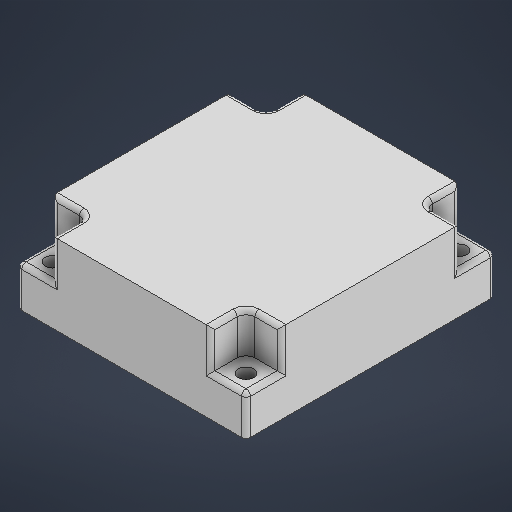
# Autodesk Inventor part: Voltage Regulator Module
Saved by Autodesk Inventor 2026.2 (Build 302298010, 298A)
## iProperties
Created: 2026-05-14
Part Number: Voltage Regulator Module
Material: Generic
Document SubType Name: Modeling
Designer: User
Density: 1 g/cm^3
Appearance: Default
Author: User
Autodesk Inventor part; units mm, degrees
ref_plane "YZ Plane" through (0, 0, 0) normal (1, 0, 0) x (0, 1, 0)
ref_plane "XZ Plane" through (0, 0, 0) normal (0, 1, 0) x (-1, 0, 0)
ref_plane "XY Plane" through (0, 0, 0) normal (0, 0, 1) x (1, 0, 0)
sketch "Sketch1" plane through (0, 0, 0) normal (0, 1, 0) x (-1, 0, 0)
  line L0 (24.75, 28) -> (-24.75, 28)
  line L1 (-25.75, 27) -> (-25.75, -27)
  line L2 (-24.75, -28) -> (24.75, -28)
  line L3 (25.75, -27) -> (25.75, 27)
  line L4 (25.75, 28) -> (-25.75, -28) construction
  line L5 (-25.75, 28) -> (25.75, -28) construction
  arc A0 (-25.75, -27) -> (-24.75, -28) centre (-24.75, -27) ccw
  arc A1 (-24.75, 28) -> (-25.75, 27) centre (-24.75, 27) ccw
  arc A2 (25.75, 27) -> (24.75, 28) centre (24.75, 27) ccw
  arc A3 (24.75, -28) -> (25.75, -27) centre (24.75, -27) ccw
  point P0 (0, 0)
  dimension "d0" = 51.5
  dimension "d1" = 56
  dimension "d16" = 1
  constraints: 12 end point, 8 point on circle, 8 point on line, 8 tangent, 4 centre point, 3 equal radius, 2 midpoint, 2 parallel, 1 horizontal, 1 perpendicular
  measures "d0" distance of L5.end L4.end
  measures "d1" distance of L4.end L5.start
  measures "d16" radius of A0
extrude "Extrusion1" add sketch "Sketch1" along normal blind 18
sketch "Sketch2" plane through (0, 18, 0) normal (0, 1, 0) x (1, 0, 0)
  line L0 (-24.75, -28) -> (24.75, -28) projected
  line L1 (-25.75, -28) -> (-17.75, -28)
  line L2 (-17.75, -28) -> (-17.75, -22)
  line L3 (-19.75, -20) -> (-25.75, -20)
  line L4 (-25.75, -20) -> (-25.75, -28)
  line L5 (24.75, 28) -> (-24.75, 28) projected
  line L6 (-25.75, 28) -> (-17.75, 28)
  line L7 (-17.75, 28) -> (-17.75, 22)
  line L8 (-19.75, 20) -> (-25.75, 20)
  line L9 (-25.75, 20) -> (-25.75, 28)
  line L10 (25.75, 28) -> (17.75, 28)
  line L11 (17.75, 28) -> (17.75, 22)
  line L12 (19.75, 20) -> (25.75, 20)
  line L13 (25.75, 20) -> (25.75, 28)
  line L14 (25.75, -28) -> (17.75, -28)
  line L15 (17.75, -28) -> (17.75, -22)
  line L16 (19.75, -20) -> (25.75, -20)
  line L17 (25.75, -20) -> (25.75, -28)
  arc A0 (-19.75, 20) -> (-17.75, 22) centre (-19.75, 22) ccw
  arc A1 (17.75, 22) -> (19.75, 20) centre (19.75, 22) ccw
  arc A2 (19.75, -20) -> (17.75, -22) centre (19.75, -22) ccw
  arc A3 (-17.75, -22) -> (-19.75, -20) centre (-19.75, -22) ccw
  point P0 (0, 0)
  point P1 (-17.75, -20)
  point P2 (-17.75, 20)
  point P3 (17.75, 20)
  point P4 (17.75, -20)
  point P5 (17.75, 28)
  point P6 (-17.75, 28)
  point P7 (17.75, -28)
  dimension "d4" = 8
  dimension "d5" = 8
  dimension "d6" = 8
  dimension "d7" = 8
  dimension "d8" = 8
  dimension "d9" = 8
  dimension "d10" = 8
  dimension "d11" = 8
  dimension "d15" = 2
  constraints: 32 end point, 8 parallel, 8 point on circle, 8 point on line, 8 tangent, 4 centre point, 4 horizontal, 4 perpendicular, 3 equal radius
  measures "d4" distance of L3.end point (-17.75, -20)
  measures "d5" distance of point (-17.75, -20) L1.end
  measures "d6" distance of point (-17.75, 20) L8.end
  measures "d7" distance of L6.end point (-17.75, 20)
  measures "d8" distance of L12.end point (17.75, 20)
  measures "d9" distance of point (17.75, 20) L10.end
  measures "d10" distance of point (17.75, -20) L16.end
  measures "d11" distance of L14.end point (17.75, -20)
  measures "d15" radius of A0
extrude "Extrusion2" cut sketch "Sketch2" against normal blind 9
sketch "Sketch3" plane through (0, 9, 0) normal (0, 1, 0) x (1, 0, 0)
  line L0 (-17.75, -22) -> (-17.75, -28) projected
  line L1 (-24.75, -28) -> (24.75, -28) projected
  line L2 (-17.75, 28) -> (-17.75, 22) projected
  line L3 (24.75, 28) -> (-24.75, 28) projected
  line L4 (25.75, 20) -> (19.75, 20) projected
  line L5 (25.75, -27) -> (25.75, 27) projected
  line L6 (19.75, -20) -> (25.75, -20) projected
  point P0 (0, 0)
  point P1 (-21.75, -24)
  point P2 (21.75, -24)
  point P3 (21.75, 24)
  point P4 (-21.75, 24)
hole "Hole1" at (-21.75, 9, 24) at (21.75, 9, 24) at (21.75, 9, -24) at (-21.75, 9, -24) direction (0, -1, 0) diameter 3.5 end through all
fillet "Fillet3" radius 1 32 edges at (25.4571, 9, 27.7071) (25.75, 9, 23.5) (21.25, 9, 28) (17.75, 13.5, 28) (18.3358, 18, 20.5858) (22.75, 18, 20) (17.75, 18, 25) (25.75, 13.5, 20) (17.75, 13.5, -28) (18.3358, 18, -20.5858) (22.75, 18, -20) (17.75, 18, -25) (25.75, 13.5, -20) (25.4571, 9, -27.7071) (21.25, 9, -28) (25.75, 9, -23.5) (-17.75, 13.5, 28) (-25.4571, 9, 27.7071) (-25.75, 9, 23.5) (-21.25, 9, 28) (-18.3358, 18, 20.5858) (-17.75, 18, 25) (-22.75, 18, 20) (-25.75, 13.5, 20) (-18.3358, 18, -20.5858) (-17.75, 18, -25) (-22.75, 18, -20) (-25.75, 13.5, -20) (-17.75, 13.5, -28) (-25.4571, 9, -27.7071) (-25.75, 9, -23.5) (-21.25, 9, -28)
body "Solid1"
